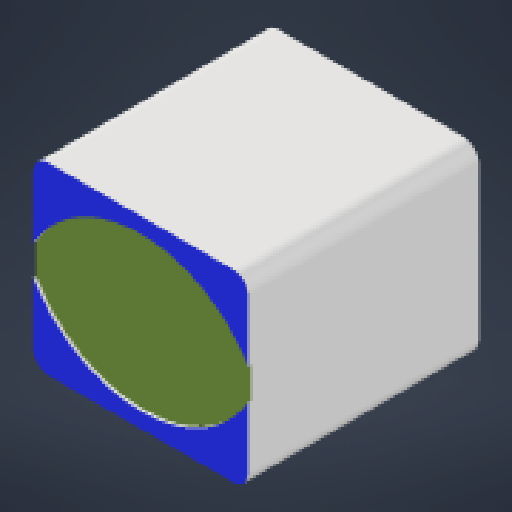
# Autodesk Inventor part: Khối pin sạc Li-ion 12V 21Ah 30A 3S MTM
Saved by Autodesk Inventor 2027 (Build 310192060, 192F)
## iProperties
Created: 2026-06-12
Part Number: Khối pin sạc Li-ion 12V 21Ah 30A 3S MTM
Material: Generic
Document SubType Name: Modeling
Designer: thita
Density: 1 g/cm^3
Appearance: Default
Author: thita
Autodesk Inventor part; units mm, degrees
ref_plane "YZ Plane" through (0, 0, 0) normal (1, 0, 0) x (0, 1, 0)
ref_plane "XZ Plane" through (0, 0, 0) normal (0, 1, 0) x (-1, 0, 0)
ref_plane "XY Plane" through (0, 0, 0) normal (0, 0, 1) x (1, 0, 0)
sketch "Sketch1" plane through (0, 0, 0) normal (0, 1, 0) x (-1, 0, 0)
  line L0 (-37.5, 60) -> (-37.5, -60)
  line L1 (-37.5, -60) -> (37.5, -60)
  line L2 (37.5, -60) -> (37.5, 60)
  line L3 (37.5, 60) -> (-37.5, 60)
  line L4 (-37.5, 60) -> (37.5, -60) construction
  line L5 (-37.5, -60) -> (37.5, 60) construction
  point P0 (0, 0)
  dimension "d0" = 120
  dimension "d1" = 75
  constraints: 12 end point, 2 midpoint, 2 parallel, 1 perpendicular, 1 vertical
  measures "d0" distance of L0.start L0.end
  measures "d1" distance of L1.end L0.end
extrude "Extrusion1" add sketch "Sketch1" along normal blind 50
fillet "Fillet1" radius 5 4 edges at (-37.5, 50, 0) (-37.5, 0, 0) (37.5, 0, 0) (37.5, 50, 0)
sketch "Sketch2" plane through (32.5, 0, -60) normal (0, 0, -1) x (-1, 0, 0)
  arc A0 (0, 50) -> (-5, 45) centre (0, 45) ccw projected
  line L0 (-5, 5) -> (-5, 45) projected
  arc A1 (-5, 5) -> (0, 0) centre (0, 5) ccw projected
  line L1 (0, 0) -> (65, 0) projected
  arc A2 (65, 0) -> (70, 5) centre (65, 5) ccw projected
  line L2 (70, 5) -> (70, 45) projected
  arc A3 (70, 45) -> (65, 50) centre (65, 45) ccw projected
  line L3 (0, 50) -> (65, 50) projected
  line L4 (70, 5) -> (70, 45) projected
  arc A4 (67.4397, 30.102) -> (-2.4397, 30.102) centre (32.5, 9.375) ccw
  arc A5 (-2.4397, 19.898) -> (67.4397, 19.898) centre (32.5, 40.625) ccw
  arc A6 (67.4397, 19.898) -> (67.4397, 30.102) centre (58.8391, 25) ccw
  arc A7 (-2.4397, 30.102) -> (-2.4397, 19.898) centre (6.1609, 25) ccw
  point P0 (32.5, 0)
  dimension "d5" = 10
  constraints: 9 point on circle, 4 centre point, 4 tangent, 1 equal radius
  measures "d5" radius of A6
extrude "Extrusion2" cut sketch "Sketch2" against normal blind 1 contours A4 A6 A5 A7
mirror "Mirror1" about plane through (0, 0, 0) normal (0, 0, 1) of "Extrusion2"
sketch "Sketch3" plane through (37.5, 5, -60) normal (0, 0, -1) x (-1, 0, 0)
  arc A0 (5, 45) -> (0, 40) centre (5, 40) ccw projected
  arc A1 (70, -5) -> (75, 0) centre (70, 0) ccw projected
  line L0 (5, 40) -> (70, 0)
  line L1 (0, -5) -> (75, -5)
  line L2 (75, -5) -> (75, 45)
  line L3 (75, 45) -> (0, 45)
  line L4 (0, 45) -> (0, -5)
  line L5 (0, -5) -> (75, 45) construction
  line L6 (75, -5) -> (0, 45) construction
  point P0 (37.5, -5)
  point P1 (37.5, 20)
  constraints: 14 end point, 3 midpoint, 2 parallel, 1 horizontal, 1 perpendicular
extrude "Extrusion3" cut sketch "Sketch3" against normal blind 45
sketch "Sketch4" plane through (37.5, 5, -15) normal (0, 0, -1) x (-1, 0, 0)
  arc A0 (5, 45) -> (0, 40) centre (5, 40) ccw projected
  line L0 (0, 40) -> (0, 45)
  line L1 (0, 45) -> (5, 45)
  line L2 (0, 45) -> (75, 45)
  line L3 (75, 45) -> (75, 45)
  line L4 (70, 50) -> (5, 50)
  line L5 (0, 45) -> (0, 45)
  arc A1 (75, 40) -> (70, 45) centre (70, 40) ccw projected
  line L6 (75, 45) -> (75, 40)
  line L7 (0, 0) -> (0, 40) projected
  line L8 (0, 20) -> (75, 20)
  line L9 (75, 40) -> (75, 0) projected
  arc A2 (0, 0) -> (5, -5) centre (5, 0) ccw
  line L10 (0, 0) -> (0, -5)
  line L11 (0, -5) -> (5, -5)
  line L12 (0, -5) -> (75, -5)
  line L13 (75, -5) -> (75, -5)
  line L14 (70, -10) -> (5, -10)
  line L15 (0, -5) -> (0, -5)
  arc A3 (70, -5) -> (75, 0) centre (70, 0) ccw
  line L16 (75, -5) -> (75, 0)
  arc A4 (5, 50) -> (0, 45) centre (5, 45) ccw
  arc A5 (75, 45) -> (70, 50) centre (70, 45) ccw
  arc A6 (70, -10) -> (75, -5) centre (70, -5) ccw
  arc A7 (0, -5) -> (5, -10) centre (5, -5) ccw
  point P0 (37.5, -5)
  point P1 (75, 50)
  point P2 (0, 50)
  point P3 (75, -10)
  point P4 (0, -10)
  point P5 (5, -5)
  dimension "d10" = 5
  dimension "d11" = 5
  constraints: 30 end point, 12 point on circle, 10 tangent, 8 point on line, 8 symmetric about line, 6 centre point, 3 equal radius, 2 midpoint, 2 parallel, 2 perpendicular, 2 vertical, 1 horizontal, 2 other
  measures "d10" distance of L2.end point (75, 50)
  measures "d11" radius of A4
extrude "Extrusion4" add sketch "Sketch4" against normal up to surface (75 mm away) contours A0 L0 L1 | L1 A4 L4 A5 L2 | L2 L6 A1 | A2 L11 L10 | L12 A6 L14 A7 L11 | L16 L12 A3
sketch "Sketch5" plane through (37.5, 5, -15) normal (0, 0, -1) x (-1, 0, 0)
  line L0 (75, -5) -> (75, 45) projected
  line L1 (72.5, -5) -> (72.5, 45)
  line L2 (75, 45) -> (75, -5) projected
  arc A0 (75, 45) -> (70, 50) centre (70, 45) ccw projected
  line L3 (70, 50) -> (5, 50) projected
  line L4 (70, 50) -> (67.5, 50)
  arc A1 (75, 45) -> (70, 50) centre (70, 45) ccw projected
  arc A2 (72.5, 45) -> (67.5, 50) centre (67.5, 45) ccw
  line L5 (37.5, 50) -> (37.5, 36.9517)
  line L6 (0, -5) -> (0, 45)
  line L7 (2.5, -5) -> (2.5, 45)
  line L8 (0, 45) -> (0, -5)
  arc A3 (5, 50) -> (0, 45) centre (5, 45) ccw
  line L9 (5, 50) -> (7.5, 50)
  arc A4 (5, 50) -> (0, 45) centre (5, 45) ccw
  arc A5 (7.5, 50) -> (2.5, 45) centre (7.5, 45) ccw
  line L10 (5, -10) -> (70, -10) projected
  line L11 (7.5, -10) -> (70, -10)
  arc A6 (2.5, -5) -> (7.5, -10) centre (7.5, -5) ccw
  line L12 (5, -10) -> (70, -10) projected
  line L13 (7.5, -10) -> (70, -10)
  arc A7 (67.5, -10) -> (72.5, -5) centre (67.5, -5) ccw
  arc A8 (0, -5) -> (5, -10) centre (5, -5) ccw projected
  arc A9 (70, -10) -> (75, -5) centre (70, -5) ccw projected
  point P0 (2.5, -5)
  dimension "d16" = 5
  dimension "d17" = 5
  constraints: 18 end point, 12 point on circle, 9 symmetric about line, 6 centre point, 5 tangent, 2 collinear, 2 point on line, 2 vertical, 1 horizontal, 1 midpoint, 3 other
  measures "d16" radius of A2
  measures "d17" radius of A6
extrude "Extrusion5" cut sketch "Sketch5" against normal up to surface (75 mm away) contours A9 L10 A7 L1 A2 L3 A0 L0 | L10 A8 L6 A3 L3 A5 L7 A6
body "Solid1"
